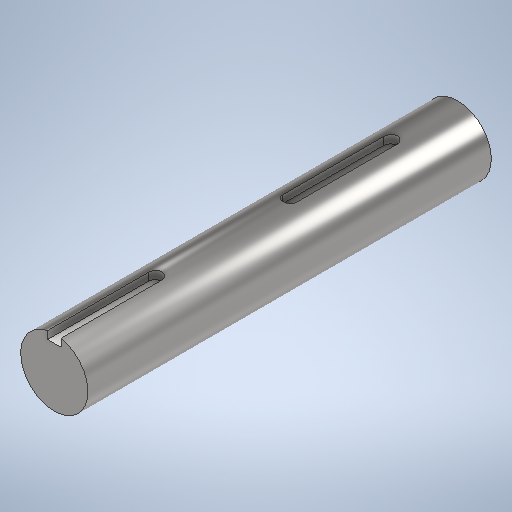
# Autodesk Inventor part: 00_Arbre_sortie
Saved by Autodesk Inventor 2025.3 (Build 293356000, 356)
## iProperties
Created: 2026-11-06
Part Number: 00_Arbre_sortie
Material: Acier, carbone
Document SubType Name: Modeling
Designer: hugoh
Density: 7.85 g/cm^3
Appearance: Semi-poli
Description: Arbre de sortie du mulitplicateur
Author: hugoh
Autodesk Inventor part; units mm, degrees
ref_plane "YZ Plane" through (0, 0, 0) normal (1, 0, 0) x (0, 1, 0)
ref_plane "XY Plane" through (0, 0, 0) normal (0, 0, 1) x (1, 0, 0)
ref_plane "Plan de construction1" through (0, 5, 0) normal (0, 1, 0) x (-1, 0, 0)
derived "11_Squelette.ipt"
sketch "Pos_Axe_Engren" plane through (0, 0, 0) normal (0, 0, 1) x (1, 0, 0)
  line L0 (-35.41, 0) -> (35.41, 0) construction
  line L1 (0, 54.2716) -> (0, -9.0453) construction
  point P0 (0, 0)
  point P1 (0, 20)
  point P2 (0, 47)
ref_plane "Av_Engren" through (0, 0, 7.5) normal (0, 0, 1) x (1, 0, 0)
ref_plane "Arr_Engren" through (0, 0, -7.5) normal (0, 0, 1) x (1, 0, 0)
ref_plane "Haut_boite" through (0, 75, 0) normal (0, 1, 0) x (-1, 0, 0)
ref_plane "Av_boite" through (0, 0, 22.5) normal (0, 0, 1) x (1, 0, 0)
ref_plane "Arr_boite" through (0, 0, -22.5) normal (0, 0, 1) x (1, 0, 0)
ref_plane "Dr_boite" through (25, 0, 0) normal (1, 0, 0) x (0, 1, 0)
ref_plane "G_boite" through (-25, 0, 0) normal (1, 0, 0) x (0, 1, 0)
ref_plane "Fd_portee_roul_Arr" through (0, 0, 17.5) normal (0, 0, 1) x (1, 0, 0)
ref_plane "Fd_portee_roul_Av" through (0, 0, -17.5) normal (0, 0, 1) x (1, 0, 0)
ref_plane "Bout_output_shaft" through (0, 0, -42.5) normal (0, 0, 1) x (1, 0, 0)
ref_plane "Bout_input_shaft" through (0, 0, 42.5) normal (0, 0, 1) x (1, 0, 0)
sketch "Esquisse4" plane through (0, 0, 0) normal (1, 0, 0) x (0, 1, 0)
  line L0 (5, 42.5) -> (0, 42.5)
  line L1 (0, 42.5) -> (0, -17.5)
  line L2 (0, -17.5) -> (5, -17.5)
  line L3 (5, -17.5) -> (5, 42.5)
  line L4 (5, 54.5) -> (5, -29.5) construction
  line L5 (0, -29.5) -> (0, 54.5) construction
  line L6 (-9.4, 42.5) -> (56.4, 42.5) construction
  line L7 (-9.4, -17.5) -> (56.4, -17.5) construction
  point P0 (0, 0)
  constraints: 8 end point, 4 collinear, 2 parallel, 1 horizontal, 1 perpendicular
revolve "Révolution2" add sketch "Esquisse4" angle 360 about axis through (0, 0, -10) along (0, 0, 1)
sketch "Esquisse5" plane through (0, 5, 0) normal (0, 1, 0) x (-1, 0, 0)
  line L0 (0, 7.5) -> (0, -7.5) construction
  line L1 (-1, 7.5) -> (-1, -7.5)
  line L2 (1, -7.5) -> (1, 7.5)
  arc A0 (1, 7.5) -> (-1, 7.5) centre (0, 7.5) ccw
  arc A1 (-1, -7.5) -> (1, -7.5) centre (0, -7.5) ccw
  line L3 (0, 42.5) -> (0, 27.5) construction
  line L4 (-1, 42.5) -> (-1, 27.5)
  line L5 (1, 27.5) -> (1, 42.5)
  arc A2 (1, 42.5) -> (-1, 42.5) centre (0, 42.5) ccw
  arc A3 (-1, 27.5) -> (1, 27.5) centre (0, 27.5) ccw
  line L6 (0, -31.3201) -> (0, 65.4204) construction
  line L7 (-10.2763, -7.5) -> (26.6576, -7.5) construction
  line L8 (-10.2763, 7.5) -> (26.6576, 7.5) construction
  line L9 (-10.2763, 42.5) -> (26.6576, 42.5) construction
  point P0 (0, 0)
  point P1 (0, 0)
  point P2 (0, 35)
  dimension "d13" = 2
  dimension "d14" = 15
  dimension "d15" = 2
  constraints: 16 end point, 8 point on circle, 8 tangent, 4 centre point, 4 point on line, 2 collinear, 2 midpoint, 2 parallel, 2 vertical
  measures "d13" distance between parallel lines of L4 L5
  measures "d14" distance of L4.start L4.end
  measures "d15" distance between parallel lines of L1 L2
extrude "Extrusion2" cut sketch "Esquisse5" against normal blind 1.25
equation "\"d13\" = Larg_clav_shaft_out"
equation "\"d14\" = Long_clav_shaft_out"
equation "\"d15\" = Larg_clav_shaft_out"
equation "\"d3\" = 0.5 * Diam_input"
equation "\"Larg_clav_shaft_out\" = 2"
equation "\"Long_clav_shaft_out\" = 15"
equation "\"Diam_input\" = 10"
